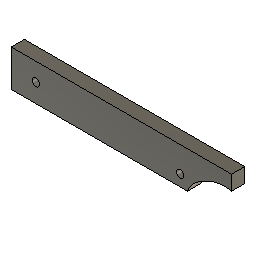
UNION (Autodesk Fusion 360 design; units mm, degrees)
part number: 2026-06-03-16-49-52-979
Autodesk Fusion 360 part; units mm, degrees
sketch "Sketch1" plane through (0, 0, 0) normal (0, 1, 0) x (1, 0, 0)
  line L0 (0, 0) -> (240, 0)
  line L1 (300, -30) -> (300, -50)
  line L2 (300, -50) -> (0, -50)
  line L3 (0, -50) -> (0, 0)
  circle A0 centre (33.7018, -25.1997) radius 5
  circle A1 centre (229.8686, -15.4379) radius 5
  spline S0 degree 5 poles (240, 0) (240.231, -0.5533) (240.7021, -1.6423) (241.4356, -3.2232) (242.4678, -5.2255) (243.8503, -7.5525) (245.33, -9.7067) (246.9154, -11.6959) (248.6202, -13.5359) (250.4629, -15.2513) (252.4616, -16.8709) (254.6287, -18.4235) (256.9667, -19.9337) (259.4605, -21.4177) (262.0838, -22.8806) (264.8097, -24.3151) (267.6236, -25.6982) (270.5269, -26.9927) (273.5663, -28.1355) (276.7354, -29.091) (279.9901, -29.8448) (283.2641, -30.3971) (286.4829, -30.7574) (289.5774, -30.9386) (292.5009, -30.9514) (295.2277, -30.8029) (297.2422, -30.5588) (298.658, -30.3063) (299.5597, -30.1072) (300, -30) knots 0 0 0 0 0 0 0.04 0.08 0.12 0.16 0.2 0.24 0.28 0.32 0.36 0.4 0.44 0.48 0.52 0.56 0.6 0.64 0.68 0.72 0.76 0.8 0.84 0.88 0.92 0.96 1 1 1 1 1 1
  line L4 (262.6406, -23.5323) -> (276.1212, -29.3834)
  point P0 (246.6032, -11.2542)
  point P1 (255.4354, -18.9243)
  point P2 (269.3809, -26.4578)
  point P3 (287.2776, -30.778)
  dimension "d2" = 50
  dimension "d4" = 10
  dimension "d5" = 10
  constraint horizontal L0
  constraint vertical L1
  constraint horizontal L2
  constraint vertical L3
  constraint coincident L0.start L3.end
  constraint midpoint P2 L4
  measures "d2" distance of L0.start L2.end
  measures "d4" diameter of A0
  measures "d5" diameter of A1
extrude "Extrude1" add sketch "Sketch1" along normal blind 18
